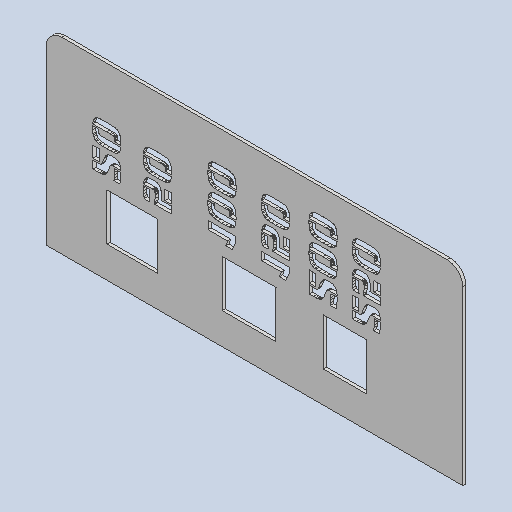
# Autodesk Inventor part: GBK-RK-0051 Cipolletti R
Saved by Autodesk Inventor 2026.2 (Build 302298000, 298)
## iProperties
Created: 2026-10-23
Part Number: GBK-RK-0051 Cipolletti R
Material: Generic
Description: Шкала расхода водослива, правая (трафарет, Saira Stencil)
Document SubType Name: Sheet Metal
Designer: admin
Density: 1 g/cm^3
Sheet Metal Rule: Default_mm
Appearance: Default
Flat Pattern Width: 12 cm
Flat Pattern Length: 26.6044 cm
Flat Pattern Area: 319.253 cm^2
Sheet Metal Width: 120,000 mm
Sheet Metal Length: 266,044 mm
Sheet Metal Area: 31925,333 mm^2
Author: admin
Autodesk Inventor part; units mm, degrees
(part 1 of 2)
ref_plane "YZ Plane" through (0, 0, 0) normal (1, 0, 0) x (0, 1, 0)
ref_plane "XZ Plane" through (0, 0, 0) normal (0, 1, 0) x (-1, 0, 0)
ref_plane "XY Plane" through (0, 0, 0) normal (0, 0, 1) x (1, 0, 0)
sketch "Sketch1" plane through (0, 0, 0) normal (0, 0, 1) x (1, 0, 0)
  line L0 (0, 0) -> (266.0444, 0)
  line L1 (266.0444, 0) -> (266.0444, 120)
  line L2 (266.0444, 120) -> (0, 120)
  line L3 (0, 120) -> (0, 0)
extrude "Plate1" add sketch "Sketch1" along normal blind 2
sketch "Sketch3" plane through (0, 0, 0) normal (0, 0, -1) x (-1, 0, 0)
  line L0 (-38.8424, 20) -> (-71.2409, 20)
  line L1 (-71.2409, 20) -> (-71.2409, 50)
  line L2 (-71.2409, 50) -> (-38.8424, 50)
  line L3 (-38.8424, 50) -> (-38.8424, 20)
  line L4 (-112.4742, 20) -> (-146.7233, 20)
  line L5 (-146.7233, 20) -> (-146.7233, 50)
  line L6 (-146.7233, 50) -> (-112.4742, 50)
  line L7 (-112.4742, 50) -> (-112.4742, 20)
  line L8 (-177.0426, 20) -> (-204.7056, 20)
  line L9 (-204.7056, 20) -> (-204.7056, 50)
  line L10 (-204.7056, 50) -> (-177.0426, 50)
  line L11 (-177.0426, 50) -> (-177.0426, 20)
  line L12 (-46.9971, 57.3557) -> (-47.3068, 58.9923)
  line L13 (-47.3068, 58.9923) -> (-47.6264, 62.3422)
  line L14 (-47.6264, 62.3422) -> (-47.6363, 64.0553)
  line L15 (-47.6363, 64.0553) -> (-43.6492, 64.0553)
  line L16 (-43.6492, 64.0553) -> (-43.7063, 63.3092)
  line L17 (-43.7063, 63.3092) -> (-43.7252, 62.0377)
  line L18 (-43.7252, 62.0377) -> (-43.6743, 60.6366)
  line L19 (-43.6743, 60.6366) -> (-43.5214, 58.9416)
  line L20 (-43.5214, 58.9416) -> (-43.3176, 57.3557)
  line L21 (-43.3176, 57.3557) -> (-46.9971, 57.3557)
  line L22 (-32.4233, 57) -> (-33.9254, 57.0251)
  line L23 (-33.9254, 57.0251) -> (-35.1079, 57.1)
  line L24 (-35.1079, 57.1) -> (-35.6017, 57.1662)
  line L25 (-35.6017, 57.1662) -> (-36.4848, 57.3838)
  line L26 (-36.4848, 57.3838) -> (-36.8737, 57.5354)
  line L27 (-36.8737, 57.5354) -> (-37.2557, 57.7333)
  line L28 (-37.2557, 57.7333) -> (-37.9388, 58.2388)
  line L29 (-37.9388, 58.2388) -> (-38.24, 58.5461)
  line L30 (-38.24, 58.5461) -> (-38.5205, 58.9015)
  line L31 (-38.5205, 58.9015) -> (-39.0401, 59.7903)
  line L32 (-39.0401, 59.7903) -> (-39.2786, 60.3239)
  line L33 (-39.2786, 60.3239) -> (-40.4773, 63.3161)
  line L34 (-40.4773, 63.3161) -> (-40.6989, 63.8374)
  line L35 (-40.6989, 63.8374) -> (-40.9007, 64.2831)
  line L36 (-40.9007, 64.2831) -> (-41.0894, 64.6306)
  line L37 (-41.0894, 64.6306) -> (-41.2722, 64.8502)
  line L38 (-41.2722, 64.8502) -> (-41.467, 64.9952)
  line L39 (-41.467, 64.9952) -> (-41.6917, 65.078)
  line L40 (-41.6917, 65.078) -> (-41.9894, 65.1169)
  line L41 (-41.9894, 65.1169) -> (-42.3949, 65.1299)
  line L42 (-42.3949, 65.1299) -> (-47.6123, 65.1299)
  line L43 (-47.6123, 65.1299) -> (-47.5003, 66.2705)
  line L44 (-47.5003, 66.2705) -> (-47.3167, 67.2393)
  line L45 (-47.3167, 67.2393) -> (-47.1917, 67.6655)
  line L46 (-47.1917, 67.6655) -> (-46.8401, 68.4267)
  line L47 (-46.8401, 68.4267) -> (-46.6136, 68.7614)
  line L48 (-46.6136, 68.7614) -> (-46.2996, 69.1088)
  line L49 (-46.2996, 69.1088) -> (-45.5137, 69.6647)
  line L50 (-45.5137, 69.6647) -> (-44.5168, 70.0352)
  line L51 (-44.5168, 70.0352) -> (-43.3092, 70.2203)
  line L52 (-43.3092, 70.2203) -> (-42.6265, 70.2436)
  line L53 (-42.6265, 70.2436) -> (-41.4782, 70.1924)
  line L54 (-41.4782, 70.1924) -> (-40.0487, 69.9237)
  line L55 (-40.0487, 69.9237) -> (-39.2911, 69.6166)
  line L56 (-39.2911, 69.6166) -> (-38.971, 69.4246)
  line L57 (-38.971, 69.4246) -> (-38.6913, 69.2178)
  line L58 (-38.6913, 69.2178) -> (-38.1799, 68.7128)
  line L59 (-38.1799, 68.7128) -> (-37.5328, 67.7279)
  line L60 (-37.5328, 67.7279) -> (-37.1813, 66.9197)
  line L61 (-37.1813, 66.9197) -> (-35.775, 63.2882)
  line L62 (-35.775, 63.2882) -> (-35.6011, 62.8697)
  line L63 (-35.6011, 62.8697) -> (-35.4396, 62.5332)
  line L64 (-35.4396, 62.5332) -> (-35.2877, 62.2824)
  line L65 (-35.2877, 62.2824) -> (-35.1358, 62.1136)
  line L66 (-35.1358, 62.1136) -> (-34.955, 62.0109)
  line L67 (-34.955, 62.0109) -> (-34.7244, 61.9579)
  line L68 (-34.7244, 61.9579) -> (-34.3859, 61.9398)
  line L69 (-34.3859, 61.9398) -> (-33.8814, 61.9339)
  line L70 (-33.8814, 61.9339) -> (-29.8424, 61.9339)
  line L71 (-29.8424, 61.9339) -> (-29.8424, 57)
  line L72 (-29.8424, 57) -> (-32.4233, 57)
  line L73 (-33.8295, 63.0085) -> (-33.8295, 70.2436)
  line L74 (-33.8295, 70.2436) -> (-29.8424, 70.2436)
  line L75 (-29.8424, 70.2436) -> (-29.8424, 63.0085)
  line L76 (-29.8424, 63.0085) -> (-33.8295, 63.0085)
  line L77 (-38.6394, 81.9568) -> (-40.4783, 81.9499)
  line L78 (-40.4783, 81.9499) -> (-41.5519, 81.929)
  line L79 (-41.5519, 81.929) -> (-42.4667, 81.852)
  line L80 (-42.4667, 81.852) -> (-43.0619, 81.7252)
  line L81 (-43.0619, 81.7252) -> (-43.2596, 81.6234)
  line L82 (-43.2596, 81.6234) -> (-43.5332, 81.3478)
  line L83 (-43.5332, 81.3478) -> (-43.6094, 81.1739)
  line L84 (-43.6094, 81.1739) -> (-43.6963, 80.6805)
  line L85 (-43.6963, 80.6805) -> (-43.7252, 79.9354)
  line L86 (-43.7252, 79.9354) -> (-43.7121, 79.5069)
  line L87 (-43.7121, 79.5069) -> (-43.6733, 78.9886)
  line L88 (-43.6733, 78.9886) -> (-47.6123, 78.9886)
  line L89 (-47.6123, 78.9886) -> (-47.6302, 79.1814)
  line L90 (-47.6302, 79.1814) -> (-47.6363, 79.4481)
  line L91 (-47.6363, 79.4481) -> (-47.6363, 79.9354)
  line L92 (-47.6363, 79.9354) -> (-47.6082, 81.2011)
  line L93 (-47.6082, 81.2011) -> (-47.3845, 83.2726)
  line L94 (-47.3845, 83.2726) -> (-47.1889, 84.0782)
  line L95 (-47.1889, 84.0782) -> (-46.9291, 84.7591)
  line L96 (-46.9291, 84.7591) -> (-46.194, 85.832)
  line L97 (-46.194, 85.832) -> (-45.7187, 86.2237)
  line L98 (-45.7187, 86.2237) -> (-45.2102, 86.5128)
  line L99 (-45.2102, 86.5128) -> (-43.9719, 86.9084)
  line L100 (-43.9719, 86.9084) -> (-43.2417, 87.0147)
  line L101 (-43.2417, 87.0147) -> (-41.3241, 87.1316)
  line L102 (-41.3241, 87.1316) -> (-38.6394, 87.1705)
  line L103 (-38.6394, 87.1705) -> (-36.2084, 87.1416)
  line L104 (-36.2084, 87.1416) -> (-34.4447, 87.0546)
  line L105 (-34.4447, 87.0546) -> (-33.7579, 86.9766)
  line L106 (-33.7579, 86.9766) -> (-32.5555, 86.689)
  line L107 (-32.5555, 86.689) -> (-32.0398, 86.4793)
  line L108 (-32.0398, 86.4793) -> (-31.5368, 86.1891)
  line L109 (-31.5368, 86.1891) -> (-30.7258, 85.4022)
  line L110 (-30.7258, 85.4022) -> (-30.4177, 84.9054)
  line L111 (-30.4177, 84.9054) -> (-30.1671, 84.3239)
  line L112 (-30.1671, 84.3239) -> (-29.8156, 82.8499)
  line L113 (-29.8156, 82.8499) -> (-29.7146, 81.9568)
  line L114 (-29.7146, 81.9568) -> (-38.6394, 81.9568)
  line L115 (-29.6386, 79.9354) -> (-29.6665, 78.6795)
  line L116 (-29.6665, 78.6795) -> (-29.8905, 76.6141)
  line L117 (-29.8905, 76.6141) -> (-30.0861, 75.8046)
  line L118 (-30.0861, 75.8046) -> (-30.3474, 75.1184)
  line L119 (-30.3474, 75.1184) -> (-31.0942, 74.0399)
  line L120 (-31.0942, 74.0399) -> (-31.5803, 73.6472)
  line L121 (-31.5803, 73.6472) -> (-32.0886, 73.358)
  line L122 (-32.0886, 73.358) -> (-33.3151, 72.9604)
  line L123 (-33.3151, 72.9604) -> (-34.0333, 72.8523)
  line L124 (-34.0333, 72.8523) -> (-35.9399, 72.7385)
  line L125 (-35.9399, 72.7385) -> (-38.6394, 72.7004)
  line L126 (-38.6394, 72.7004) -> (-41.0674, 72.7285)
  line L127 (-41.0674, 72.7285) -> (-42.8303, 72.8124)
  line L128 (-42.8303, 72.8124) -> (-43.5183, 72.8919)
  line L129 (-43.5183, 72.8919) -> (-44.7208, 73.1816)
  line L130 (-44.7208, 73.1816) -> (-45.2352, 73.3915)
  line L131 (-45.2352, 73.3915) -> (-45.7397, 73.6814)
  line L132 (-45.7397, 73.6814) -> (-46.5507, 74.4666)
  line L133 (-46.5507, 74.4666) -> (-46.8573, 74.9616)
  line L134 (-46.8573, 74.9616) -> (-47.1078, 75.5446)
  line L135 (-47.1078, 75.5446) -> (-47.4594, 77.0209)
  line L136 (-47.4594, 77.0209) -> (-47.5604, 77.914)
  line L137 (-47.5604, 77.914) -> (-38.6394, 77.914)
  line L138 (-38.6394, 77.914) -> (-36.8156, 77.9209)
  line L139 (-36.8156, 77.9209) -> (-35.7471, 77.9419)
  line L140 (-35.7471, 77.9419) -> (-34.8523, 78.025)
  line L141 (-34.8523, 78.025) -> (-34.213, 78.1697)
  line L142 (-34.213, 78.1697) -> (-34.0169, 78.2707)
  line L143 (-34.0169, 78.2707) -> (-33.7434, 78.5381)
  line L144 (-33.7434, 78.5381) -> (-33.6656, 78.7051)
  line L145 (-33.6656, 78.7051) -> (-33.5787, 79.1924)
  line L146 (-33.5787, 79.1924) -> (-33.5498, 79.9354)
  line L147 (-33.5498, 79.9354) -> (-33.5498, 80.4468)
  line L148 (-33.5498, 80.4468) -> (-33.5628, 80.6457)
  line L149 (-33.5628, 80.6457) -> (-33.6017, 80.8822)
  line L150 (-33.6017, 80.8822) -> (-29.6627, 80.8822)
  line L151 (-29.6627, 80.8822) -> (-29.6448, 80.6894)
  line L152 (-29.6448, 80.6894) -> (-29.6386, 80.4228)
  line L153 (-29.6386, 80.4228) -> (-29.6386, 79.9354)
  line L154 (-67.7381, 64.978) -> (-68.3213, 64.955)
  line L155 (-68.3213, 64.955) -> (-68.7449, 64.8863)
  line L156 (-68.7449, 64.8863) -> (-69.0505, 64.7502)
  line L157 (-69.0505, 64.7502) -> (-69.2721, 64.5186)
  line L158 (-69.2721, 64.5186) -> (-69.423, 64.1841)
  line L159 (-69.423, 64.1841) -> (-69.5158, 63.7477)
  line L160 (-69.5158, 63.7477) -> (-69.5639, 63.1553)
  line L161 (-69.5639, 63.1553) -> (-69.5797, 62.3453)
  line L162 (-69.5797, 62.3453) -> (-69.5409, 60.6056)
  line L163 (-69.5409, 60.6056) -> (-69.424, 58.7657)
  line L164 (-69.424, 58.7657) -> (-69.3419, 57.7739)
  line L165 (-69.3419, 57.7739) -> (-69.2962, 57.2038)
  line L166 (-69.2962, 57.2038) -> (-79.831, 57.2038)
  line L167 (-79.831, 57.2038) -> (-79.831, 61.5263)
  line L168 (-79.831, 61.5263) -> (-73.339, 61.5263)
  line L169 (-73.339, 61.5263) -> (-73.415, 62.3693)
  line L170 (-73.415, 62.3693) -> (-73.472, 63.8784)
  line L171 (-73.472, 63.8784) -> (-73.4909, 64.8742)
  line L172 (-73.4909, 64.8742) -> (-73.4681, 65.6073)
  line L173 (-73.4681, 65.6073) -> (-73.2858, 66.9051)
  line L174 (-73.2858, 66.9051) -> (-72.9212, 67.9787)
  line L175 (-72.9212, 67.9787) -> (-72.3746, 68.8281)
  line L176 (-72.3746, 68.8281) -> (-72.0327, 69.1689)
  line L177 (-72.0327, 69.1689) -> (-71.6827, 69.4295)
  line L178 (-71.6827, 69.4295) -> (-70.8717, 69.825)
  line L179 (-70.8717, 69.825) -> (-70.4107, 69.96)
  line L180 (-70.4107, 69.96) -> (-69.908, 70.0613)
  line L181 (-69.908, 70.0613) -> (-68.7636, 70.1771)
  line L182 (-68.7636, 70.1771) -> (-68.1216, 70.1916)
  line L183 (-68.1216, 70.1916) -> (-67.397, 70.1771)
  line L184 (-67.397, 70.1771) -> (-66.1306, 70.0613)
  line L185 (-66.1306, 70.0613) -> (-65.5888, 69.96)
  line L186 (-65.5888, 69.96) -> (-65.0966, 69.825)
  line L187 (-65.0966, 69.825) -> (-64.2278, 69.4295)
  line L188 (-64.2278, 69.4295) -> (-63.8509, 69.1689)
  line L189 (-63.8509, 69.1689) -> (-63.5116, 68.8593)
  line L190 (-63.5116, 68.8593) -> (-62.9422, 68.0603)
  line L191 (-62.9422, 68.0603) -> (-62.7124, 67.5709)
  line L192 (-62.7124, 67.5709) -> (-62.5191, 67.0207)
  line L193 (-62.5191, 67.0207) -> (-62.2314, 65.7244)
  line L194 (-62.2314, 65.7244) -> (-62.1371, 64.978)
  line L195 (-62.1371, 64.978) -> (-67.7381, 64.978)
  line L196 (-79.831, 62.601) -> (-79.831, 68.8892)
  line L197 (-79.831, 68.8892) -> (-75.868, 68.8892)
  line L198 (-75.868, 68.8892) -> (-75.868, 62.601)
  line L199 (-75.868, 62.601) -> (-79.831, 62.601)
  line L200 (-62.0371, 62.6769) -> (-62.0821, 61.1249)
  line L201 (-62.0821, 61.1249) -> (-62.2169, 59.5929)
  line L202 (-62.2169, 59.5929) -> (-62.4127, 58.1856)
  line L203 (-62.4127, 58.1856) -> (-62.6485, 57)
  line L204 (-62.6485, 57) -> (-66.3078, 57)
  line L205 (-66.3078, 57) -> (-66.161, 58.4221)
  line L206 (-66.161, 58.4221) -> (-65.9933, 60.9789)
  line L207 (-65.9933, 60.9789) -> (-65.9723, 62.1136)
  line L208 (-65.9723, 62.1136) -> (-65.9854, 63.1624)
  line L209 (-65.9854, 63.1624) -> (-66.0242, 63.9034)
  line L210 (-66.0242, 63.9034) -> (-62.0611, 63.9034)
  line L211 (-62.0611, 63.9034) -> (-62.0433, 63.3931)
  line L212 (-62.0433, 63.3931) -> (-62.0371, 62.6769)
  line L213 (-71.0379, 81.853) -> (-72.8767, 81.8461)
  line L214 (-72.8767, 81.8461) -> (-73.9504, 81.8252)
  line L215 (-73.9504, 81.8252) -> (-74.8652, 81.7482)
  line L216 (-74.8652, 81.7482) -> (-75.4604, 81.6214)
  line L217 (-75.4604, 81.6214) -> (-75.6581, 81.5194)
  line L218 (-75.6581, 81.5194) -> (-75.9316, 81.2438)
  line L219 (-75.9316, 81.2438) -> (-76.0078, 81.0701)
  line L220 (-76.0078, 81.0701) -> (-76.0948, 80.5767)
  line L221 (-76.0948, 80.5767) -> (-76.1236, 79.8316)
  line L222 (-76.1236, 79.8316) -> (-76.1106, 79.4031)
  line L223 (-76.1106, 79.4031) -> (-76.0717, 78.8848)
  line L224 (-76.0717, 78.8848) -> (-80.0108, 78.8848)
  line L225 (-80.0108, 78.8848) -> (-80.0287, 79.0776)
  line L226 (-80.0287, 79.0776) -> (-80.0348, 79.3443)
  line L227 (-80.0348, 79.3443) -> (-80.0348, 79.8316)
  line L228 (-80.0348, 79.8316) -> (-80.0067, 81.0972)
  line L229 (-80.0067, 81.0972) -> (-79.783, 83.1688)
  line L230 (-79.783, 83.1688) -> (-79.5874, 83.9744)
  line L231 (-79.5874, 83.9744) -> (-79.3276, 84.6553)
  line L232 (-79.3276, 84.6553) -> (-78.5925, 85.7279)
  line L233 (-78.5925, 85.7279) -> (-78.1172, 86.1199)
  line L234 (-78.1172, 86.1199) -> (-77.6086, 86.4088)
  line L235 (-77.6086, 86.4088) -> (-76.3704, 86.8043)
  line L236 (-76.3704, 86.8043) -> (-75.6402, 86.9107)
  line L237 (-75.6402, 86.9107) -> (-73.7225, 87.0275)
  line L238 (-73.7225, 87.0275) -> (-71.0379, 87.0666)
  line L239 (-71.0379, 87.0666) -> (-68.6069, 87.0375)
  line L240 (-68.6069, 87.0375) -> (-66.8432, 86.9508)
  line L241 (-66.8432, 86.9508) -> (-66.1564, 86.8728)
  line L242 (-66.1564, 86.8728) -> (-64.9539, 86.5852)
  line L243 (-64.9539, 86.5852) -> (-64.4382, 86.3755)
  line L244 (-64.4382, 86.3755) -> (-63.9353, 86.0853)
  line L245 (-63.9353, 86.0853) -> (-63.1243, 85.2984)
  line L246 (-63.1243, 85.2984) -> (-62.8162, 84.8013)
  line L247 (-62.8162, 84.8013) -> (-62.5656, 84.2201)
  line L248 (-62.5656, 84.2201) -> (-62.214, 82.7459)
  line L249 (-62.214, 82.7459) -> (-62.1131, 81.853)
  line L250 (-62.1131, 81.853) -> (-71.0379, 81.853)
  line L251 (-62.0371, 79.8316) -> (-62.065, 78.5757)
  line L252 (-62.065, 78.5757) -> (-62.289, 76.5103)
  line L253 (-62.289, 76.5103) -> (-62.4846, 75.7008)
  line L254 (-62.4846, 75.7008) -> (-62.7459, 75.0146)
  line L255 (-62.7459, 75.0146) -> (-63.4927, 73.9359)
  line L256 (-63.4927, 73.9359) -> (-63.9788, 73.5434)
  line L257 (-63.9788, 73.5434) -> (-64.4871, 73.2539)
  line L258 (-64.4871, 73.2539) -> (-65.7136, 72.8566)
  line L259 (-65.7136, 72.8566) -> (-66.4318, 72.7485)
  line L260 (-66.4318, 72.7485) -> (-68.3384, 72.6344)
  line L261 (-68.3384, 72.6344) -> (-71.0379, 72.5966)
  line L262 (-71.0379, 72.5966) -> (-73.4658, 72.6245)
  line L263 (-73.4658, 72.6245) -> (-75.2288, 72.7086)
  line L264 (-75.2288, 72.7086) -> (-75.9168, 72.7881)
  line L265 (-75.9168, 72.7881) -> (-77.1193, 73.0778)
  line L266 (-77.1193, 73.0778) -> (-77.6337, 73.2877)
  line L267 (-77.6337, 73.2877) -> (-78.1382, 73.5776)
  line L268 (-78.1382, 73.5776) -> (-78.9492, 74.3626)
  line L269 (-78.9492, 74.3626) -> (-79.2558, 74.8578)
  line L270 (-79.2558, 74.8578) -> (-79.5063, 75.4408)
  line L271 (-79.5063, 75.4408) -> (-79.8579, 76.9168)
  line L272 (-79.8579, 76.9168) -> (-79.9589, 77.8102)
  line L273 (-79.9589, 77.8102) -> (-71.0379, 77.8102)
  line L274 (-71.0379, 77.8102) -> (-69.2141, 77.8171)
  line L275 (-69.2141, 77.8171) -> (-68.1456, 77.8381)
  line L276 (-68.1456, 77.8381) -> (-67.2507, 77.9209)
  line L277 (-67.2507, 77.9209) -> (-66.6115, 78.0659)
  line L278 (-66.6115, 78.0659) -> (-66.4154, 78.1666)
  line L279 (-66.4154, 78.1666) -> (-66.1418, 78.4343)
  line L280 (-66.1418, 78.4343) -> (-66.0641, 78.601)
  line L281 (-66.0641, 78.601) -> (-65.9772, 79.0886)
  line L282 (-65.9772, 79.0886) -> (-65.9483, 79.8316)
  line L283 (-65.9483, 79.8316) -> (-65.9483, 80.343)
  line L284 (-65.9483, 80.343) -> (-65.9613, 80.5416)
  line L285 (-65.9613, 80.5416) -> (-66.0002, 80.7784)
  line L286 (-66.0002, 80.7784) -> (-62.0611, 80.7784)
  line L287 (-62.0611, 80.7784) -> (-62.0433, 80.5856)
  line L288 (-62.0433, 80.5856) -> (-62.0371, 80.3189)
  line L289 (-62.0371, 80.3189) -> (-62.0371, 79.8316)
  line L290 (-115.9267, 60.2479) -> (-114.7002, 57)
  line L291 (-114.7002, 57) -> (-118.6873, 57)
  line L292 (-118.6873, 57) -> (-121.0644, 61.9618)
  line L293 (-121.0644, 61.9618) -> (-121.0644, 65.3616)
  line L294 (-121.0644, 65.3616) -> (-103.4742, 65.3616)
  line L295 (-103.4742, 65.3616) -> (-103.4742, 60.2479)
  line L296 (-103.4742, 60.2479) -> (-115.9267, 60.2479)
  line L297 (-112.2712, 77.4824) -> (-114.1101, 77.4755)
  line L298 (-114.1101, 77.4755) -> (-115.1837, 77.4545)
  line L299 (-115.1837, 77.4545) -> (-116.0985, 77.3776)
  line L300 (-116.0985, 77.3776) -> (-116.6938, 77.2508)
  line L301 (-116.6938, 77.2508) -> (-116.8914, 77.149)
  line L302 (-116.8914, 77.149) -> (-117.165, 76.8734)
  line L303 (-117.165, 76.8734) -> (-117.2412, 76.6995)
  line L304 (-117.2412, 76.6995) -> (-117.3281, 76.2061)
  line L305 (-117.3281, 76.2061) -> (-117.357, 75.461)
  line L306 (-117.357, 75.461) -> (-117.344, 75.0325)
  line L307 (-117.344, 75.0325) -> (-117.3051, 74.5142)
  line L308 (-117.3051, 74.5142) -> (-121.2441, 74.5142)
  line L309 (-121.2441, 74.5142) -> (-121.262, 74.707)
  line L310 (-121.262, 74.707) -> (-121.2682, 74.9737)
  line L311 (-121.2682, 74.9737) -> (-121.2682, 75.461)
  line L312 (-121.2682, 75.461) -> (-121.24, 76.7266)
  line L313 (-121.24, 76.7266) -> (-121.0163, 78.7982)
  line L314 (-121.0163, 78.7982) -> (-120.8207, 79.6038)
  line L315 (-120.8207, 79.6038) -> (-120.5609, 80.2847)
  line L316 (-120.5609, 80.2847) -> (-119.8259, 81.3575)
  line L317 (-119.8259, 81.3575) -> (-119.3505, 81.7492)
  line L318 (-119.3505, 81.7492) -> (-118.842, 82.0384)
  line L319 (-118.842, 82.0384) -> (-117.6037, 82.4339)
  line L320 (-117.6037, 82.4339) -> (-116.8735, 82.5403)
  line L321 (-116.8735, 82.5403) -> (-114.9559, 82.6572)
  line L322 (-114.9559, 82.6572) -> (-112.2712, 82.696)
  line L323 (-112.2712, 82.696) -> (-109.8402, 82.6671)
  line L324 (-109.8402, 82.6671) -> (-108.0765, 82.5802)
  line L325 (-108.0765, 82.5802) -> (-107.3898, 82.5022)
  line L326 (-107.3898, 82.5022) -> (-106.1873, 82.2146)
  line L327 (-106.1873, 82.2146) -> (-105.6716, 82.0049)
  line L328 (-105.6716, 82.0049) -> (-105.1686, 81.7147)
  line L329 (-105.1686, 81.7147) -> (-104.3576, 80.9277)
  line L330 (-104.3576, 80.9277) -> (-104.0495, 80.4309)
  line L331 (-104.0495, 80.4309) -> (-103.799, 79.8495)
  line L332 (-103.799, 79.8495) -> (-103.4474, 78.3755)
  line L333 (-103.4474, 78.3755) -> (-103.3464, 77.4824)
  line L334 (-103.3464, 77.4824) -> (-112.2712, 77.4824)
  line L335 (-103.2705, 75.461) -> (-103.2983, 74.2051)
  line L336 (-103.2983, 74.2051) -> (-103.5223, 72.1397)
  line L337 (-103.5223, 72.1397) -> (-103.7179, 71.3302)
  line L338 (-103.7179, 71.3302) -> (-103.9792, 70.6439)
  line L339 (-103.9792, 70.6439) -> (-104.7261, 69.5655)
  line L340 (-104.7261, 69.5655) -> (-105.2121, 69.1728)
  line L341 (-105.2121, 69.1728) -> (-105.7204, 68.8836)
  line L342 (-105.7204, 68.8836) -> (-106.9469, 68.486)
  line L343 (-106.9469, 68.486) -> (-107.6651, 68.3778)
  line L344 (-107.6651, 68.3778) -> (-109.5717, 68.2641)
  line L345 (-109.5717, 68.2641) -> (-112.2712, 68.226)
  line L346 (-112.2712, 68.226) -> (-114.6992, 68.2541)
  line L347 (-114.6992, 68.2541) -> (-116.4621, 68.338)
  line L348 (-116.4621, 68.338) -> (-117.1502, 68.4175)
  line L349 (-117.1502, 68.4175) -> (-118.3526, 68.7072)
  line L350 (-118.3526, 68.7072) -> (-118.8671, 68.9171)
  line L351 (-118.8671, 68.9171) -> (-119.3715, 69.207)
  line L352 (-119.3715, 69.207) -> (-120.1825, 69.992)
  line L353 (-120.1825, 69.992) -> (-120.4891, 70.4872)
  line L354 (-120.4891, 70.4872) -> (-120.7397, 71.0702)
  line L355 (-120.7397, 71.0702) -> (-121.0912, 72.5465)
  line L356 (-121.0912, 72.5465) -> (-121.1922, 73.4396)
  line L357 (-121.1922, 73.4396) -> (-112.2712, 73.4396)
  line L358 (-112.2712, 73.4396) -> (-110.4475, 73.4465)
  line L359 (-110.4475, 73.4465) -> (-109.379, 73.4674)
  line L360 (-109.379, 73.4674) -> (-108.4841, 73.5503)
  line L361 (-108.4841, 73.5503) -> (-107.8449, 73.6953)
  line L362 (-107.8449, 73.6953) -> (-107.6488, 73.796)
  line L363 (-107.6488, 73.796) -> (-107.3752, 74.0637)
  line L364 (-107.3752, 74.0637) -> (-107.2975, 74.2307)
  line L365 (-107.2975, 74.2307) -> (-107.2105, 74.718)
  line L366 (-107.2105, 74.718) -> (-107.1816, 75.461)
  line L367 (-107.1816, 75.461) -> (-107.1816, 75.9724)
  line L368 (-107.1816, 75.9724) -> (-107.1947, 76.171)
  line L369 (-107.1947, 76.171) -> (-107.2335, 76.4078)
  line L370 (-107.2335, 76.4078) -> (-103.2945, 76.4078)
  line L371 (-103.2945, 76.4078) -> (-103.2766, 76.215)
  line L372 (-103.2766, 76.215) -> (-103.2705, 75.9483)
  line L373 (-103.2705, 75.9483) -> (-103.2705, 75.461)
  line L374 (-112.2712, 94.3574) -> (-114.1101, 94.3505)
  line L375 (-114.1101, 94.3505) -> (-115.1837, 94.3295)
  line L376 (-115.1837, 94.3295) -> (-116.0985, 94.2526)
  line L377 (-116.0985, 94.2526) -> (-116.6938, 94.1258)
  line L378 (-116.6938, 94.1258) -> (-116.8914, 94.024)
  line L379 (-116.8914, 94.024) -> (-117.165, 93.7484)
  line L380 (-117.165, 93.7484) -> (-117.2412, 93.5745)
  line L381 (-117.2412, 93.5745) -> (-117.3281, 93.0811)
  line L382 (-117.3281, 93.0811) -> (-117.357, 92.336)
  line L383 (-117.357, 92.336) -> (-117.344, 91.9075)
  line L384 (-117.344, 91.9075) -> (-117.3051, 91.3892)
  line L385 (-117.3051, 91.3892) -> (-121.2441, 91.3892)
  line L386 (-121.2441, 91.3892) -> (-121.262, 91.582)
  line L387 (-121.262, 91.582) -> (-121.2682, 91.8487)
  line L388 (-121.2682, 91.8487) -> (-121.2682, 92.336)
  line L389 (-121.2682, 92.336) -> (-121.24, 93.6016)
  line L390 (-121.24, 93.6016) -> (-121.0163, 95.6732)
  line L391 (-121.0163, 95.6732) -> (-120.8207, 96.4788)
  line L392 (-120.8207, 96.4788) -> (-120.5609, 97.1597)
  line L393 (-120.5609, 97.1597) -> (-119.8259, 98.2325)
  line L394 (-119.8259, 98.2325) -> (-119.3505, 98.6242)
  line L395 (-119.3505, 98.6242) -> (-118.842, 98.9134)
  line L396 (-118.842, 98.9134) -> (-117.6037, 99.3089)
  line L397 (-117.6037, 99.3089) -> (-116.8735, 99.4153)
  line L398 (-116.8735, 99.4153) -> (-114.9559, 99.5322)
  line L399 (-114.9559, 99.5322) -> (-112.2712, 99.571)
  line L400 (-112.2712, 99.571) -> (-109.8402, 99.5421)
  line L401 (-109.8402, 99.5421) -> (-108.0765, 99.4552)
  line L402 (-108.0765, 99.4552) -> (-107.3898, 99.3772)
  line L403 (-107.3898, 99.3772) -> (-106.1873, 99.0896)
  line L404 (-106.1873, 99.0896) -> (-105.6716, 98.8799)
  line L405 (-105.6716, 98.8799) -> (-105.1686, 98.5897)
  line L406 (-105.1686, 98.5897) -> (-104.3576, 97.8027)
  line L407 (-104.3576, 97.8027) -> (-104.0495, 97.3059)
  line L408 (-104.0495, 97.3059) -> (-103.799, 96.7245)
  line L409 (-103.799, 96.7245) -> (-103.4474, 95.2505)
  line L410 (-103.4474, 95.2505) -> (-103.3464, 94.3574)
  line L411 (-103.3464, 94.3574) -> (-112.2712, 94.3574)
  line L412 (-103.2705, 92.336) -> (-103.2983, 91.0801)
  line L413 (-103.2983, 91.0801) -> (-103.5223, 89.0147)
  line L414 (-103.5223, 89.0147) -> (-103.7179, 88.2052)
  line L415 (-103.7179, 88.2052) -> (-103.9792, 87.5189)
  line L416 (-103.9792, 87.5189) -> (-104.7261, 86.4405)
  line L417 (-104.7261, 86.4405) -> (-105.2121, 86.0478)
  line L418 (-105.2121, 86.0478) -> (-105.7204, 85.7586)
  line L419 (-105.7204, 85.7586) -> (-106.9469, 85.361)
  line L420 (-106.9469, 85.361) -> (-107.6651, 85.2528)
  line L421 (-107.6651, 85.2528) -> (-109.5717, 85.1391)
  line L422 (-109.5717, 85.1391) -> (-112.2712, 85.101)
  line L423 (-112.2712, 85.101) -> (-114.6992, 85.1291)
  line L424 (-114.6992, 85.1291) -> (-116.4621, 85.213)
  line L425 (-116.4621, 85.213) -> (-117.1502, 85.2925)
  line L426 (-117.1502, 85.2925) -> (-118.3526, 85.5822)
  line L427 (-118.3526, 85.5822) -> (-118.8671, 85.7921)
  line L428 (-118.8671, 85.7921) -> (-119.3715, 86.082)
  line L429 (-119.3715, 86.082) -> (-120.1825, 86.867)
  line L430 (-120.1825, 86.867) -> (-120.4891, 87.3622)
  line L431 (-120.4891, 87.3622) -> (-120.7397, 87.9452)
  line L432 (-120.7397, 87.9452) -> (-121.0912, 89.4215)
  line L433 (-121.0912, 89.4215) -> (-121.1922, 90.3146)
  line L434 (-121.1922, 90.3146) -> (-112.2712, 90.3146)
  line L435 (-112.2712, 90.3146) -> (-110.4475, 90.3215)
  line L436 (-110.4475, 90.3215) -> (-109.379, 90.3424)
  line L437 (-109.379, 90.3424) -> (-108.4841, 90.4253)
  line L438 (-108.4841, 90.4253) -> (-107.8449, 90.5703)
  line L439 (-107.8449, 90.5703) -> (-107.6488, 90.671)
  line L440 (-107.6488, 90.671) -> (-107.3752, 90.9387)
  line L441 (-107.3752, 90.9387) -> (-107.2975, 91.1057)
  line L442 (-107.2975, 91.1057) -> (-107.2105, 91.593)
  line L443 (-107.2105, 91.593) -> (-107.1816, 92.336)
  line L444 (-107.1816, 92.336) -> (-107.1816, 92.8474)
  line L445 (-107.1816, 92.8474) -> (-107.1947, 93.046)
  line L446 (-107.1947, 93.046) -> (-107.2335, 93.2828)
  line L447 (-107.2335, 93.2828) -> (-103.2945, 93.2828)
  line L448 (-103.2945, 93.2828) -> (-103.2766, 93.09)
  line L449 (-103.2766, 93.09) -> (-103.2705, 92.8233)
  line L450 (-103.2705, 92.8233) -> (-103.2705, 92.336)
  line L451 (-150.1758, 60.2479) -> (-148.9493, 57)
  line L452 (-148.9493, 57) -> (-152.9364, 57)
  line L453 (-152.9364, 57) -> (-155.3134, 61.9618)
  line L454 (-155.3134, 61.9618) -> (-155.3134, 65.3616)
  line L455 (-155.3134, 65.3616) -> (-137.7233, 65.3616)
  line L456 (-137.7233, 65.3616) -> (-137.7233, 60.2479)
  line L457 (-137.7233, 60.2479) -> (-150.1758, 60.2479)
  line L458 (-143.2205, 76.6635) -> (-143.8037, 76.6405)
  line L459 (-143.8037, 76.6405) -> (-144.2273, 76.5717)
  line L460 (-144.2273, 76.5717) -> (-144.5329, 76.4359)
  line L461 (-144.5329, 76.4359) -> (-144.7546, 76.204)
  line L462 (-144.7546, 76.204) -> (-144.9054, 75.8696)
  line L463 (-144.9054, 75.8696) -> (-144.9982, 75.4331)
  line L464 (-144.9982, 75.4331) -> (-145.0463, 74.8407)
  line L465 (-145.0463, 74.8407) -> (-145.0621, 74.0307)
  line L466 (-145.0621, 74.0307) -> (-145.0233, 72.2911)
  line L467 (-145.0233, 72.2911) -> (-144.9064, 70.4512)
  line L468 (-144.9064, 70.4512) -> (-144.8244, 69.4594)
  line L469 (-144.8244, 69.4594) -> (-144.7786, 68.8892)
  line L470 (-144.7786, 68.8892) -> (-155.3134, 68.8892)
  line L471 (-155.3134, 68.8892) -> (-155.3134, 73.2118)
  line L472 (-155.3134, 73.2118) -> (-148.8214, 73.2118)
  line L473 (-148.8214, 73.2118) -> (-148.8974, 74.0547)
  line L474 (-148.8974, 74.0547) -> (-148.9544, 75.5638)
  line L475 (-148.9544, 75.5638) -> (-148.9733, 76.5597)
  line L476 (-148.9733, 76.5597) -> (-148.9506, 77.2927)
  line L477 (-148.9506, 77.2927) -> (-148.7682, 78.5905)
  line L478 (-148.7682, 78.5905) -> (-148.4036, 79.6641)
  line L479 (-148.4036, 79.6641) -> (-147.857, 80.5138)
  line L480 (-147.857, 80.5138) -> (-147.5152, 80.8543)
  line L481 (-147.5152, 80.8543) -> (-147.1651, 81.1149)
  line L482 (-147.1651, 81.1149) -> (-146.3541, 81.5104)
  line L483 (-146.3541, 81.5104) -> (-145.8931, 81.6454)
  line L484 (-145.8931, 81.6454) -> (-145.3904, 81.7467)
  line L485 (-145.3904, 81.7467) -> (-144.246, 81.8625)
  line L486 (-144.246, 81.8625) -> (-143.604, 81.8771)
  line L487 (-143.604, 81.8771) -> (-142.8794, 81.8625)
  line L488 (-142.8794, 81.8625) -> (-141.613, 81.7467)
  line L489 (-141.613, 81.7467) -> (-141.0712, 81.6454)
  line L490 (-141.0712, 81.6454) -> (-140.579, 81.5104)
  line L491 (-140.579, 81.5104) -> (-139.7102, 81.1149)
  line L492 (-139.7102, 81.1149) -> (-139.3333, 80.8543)
  line L493 (-139.3333, 80.8543) -> (-138.994, 80.5447)
  line L494 (-138.994, 80.5447) -> (-138.4246, 79.7457)
  line L495 (-138.4246, 79.7457) -> (-138.1948, 79.2563)
  line L496 (-138.1948, 79.2563) -> (-138.0015, 78.7064)
  line L497 (-138.0015, 78.7064) -> (-137.7138, 77.4098)
  line L498 (-137.7138, 77.4098) -> (-137.6195, 76.6635)
  line L499 (-137.6195, 76.6635) -> (-143.2205, 76.6635)
  line L500 (-155.3134, 74.2864) -> (-155.3134, 80.5746)
  line L501 (-155.3134, 80.5746) -> (-151.3504, 80.5746)
  line L502 (-151.3504, 80.5746) -> (-151.3504, 74.2864)
  line L503 (-151.3504, 74.2864) -> (-155.3134, 74.2864)
  line L504 (-137.5195, 74.3623) -> (-137.5645, 72.8103)
  line L505 (-137.5645, 72.8103) -> (-137.6993, 71.2783)
  line L506 (-137.6993, 71.2783) -> (-137.8951, 69.871)
  line L507 (-137.8951, 69.871) -> (-138.1309, 68.6854)
  line L508 (-138.1309, 68.6854) -> (-141.7902, 68.6854)
  line L509 (-141.7902, 68.6854) -> (-141.6434, 70.1078)
  line L510 (-141.6434, 70.1078) -> (-141.4757, 72.6646)
  line L511 (-141.4757, 72.6646) -> (-141.4547, 73.7991)
  line L512 (-141.4547, 73.7991) -> (-141.4678, 74.8479)
  line L513 (-141.4678, 74.8479) -> (-141.5066, 75.5888)
  line L514 (-141.5066, 75.5888) -> (-137.5436, 75.5888)
  line L515 (-137.5436, 75.5888) -> (-137.5257, 75.0785)
  line L516 (-137.5257, 75.0785) -> (-137.5195, 74.3623)
  line L517 (-146.5203, 93.5385) -> (-148.3592, 93.5316)
  line L518 (-148.3592, 93.5316) -> (-149.4328, 93.5106)
  line L519 (-149.4328, 93.5106) -> (-150.3476, 93.4336)
  line L520 (-150.3476, 93.4336) -> (-150.9428, 93.3068)
  line L521 (-150.9428, 93.3068) -> (-151.1405, 93.2051)
  line L522 (-151.1405, 93.2051) -> (-151.414, 92.9292)
  line L523 (-151.414, 92.9292) -> (-151.4902, 92.7556)
  line L524 (-151.4902, 92.7556) -> (-151.5772, 92.2621)
  line L525 (-151.5772, 92.2621) -> (-151.6061, 91.517)
  line L526 (-151.6061, 91.517) -> (-151.593, 91.0885)
  line L527 (-151.593, 91.0885) -> (-151.5542, 90.5703)
  line L528 (-151.5542, 90.5703) -> (-155.4932, 90.5703)
  line L529 (-155.4932, 90.5703) -> (-155.5111, 90.763)
  line L530 (-155.5111, 90.763) -> (-155.5172, 91.0297)
  line L531 (-155.5172, 91.0297) -> (-155.5172, 91.517)
  line L532 (-155.5172, 91.517) -> (-155.4891, 92.7827)
  line L533 (-155.4891, 92.7827) -> (-155.2654, 94.8542)
  line L534 (-155.2654, 94.8542) -> (-155.0698, 95.6599)
  line L535 (-155.0698, 95.6599) -> (-154.81, 96.3407)
  line L536 (-154.81, 96.3407) -> (-154.0749, 97.4136)
  line L537 (-154.0749, 97.4136) -> (-153.5996, 97.8053)
  line L538 (-153.5996, 97.8053) -> (-153.0911, 98.0945)
  line L539 (-153.0911, 98.0945) -> (-151.8528, 98.4897)
  line L540 (-151.8528, 98.4897) -> (-151.1226, 98.5964)
  line L541 (-151.1226, 98.5964) -> (-149.205, 98.7132)
  line L542 (-149.205, 98.7132) -> (-146.5203, 98.7521)
  line L543 (-146.5203, 98.7521) -> (-144.0893, 98.7232)
  line L544 (-144.0893, 98.7232) -> (-142.3256, 98.6362)
  line L545 (-142.3256, 98.6362) -> (-141.6388, 98.5583)
  line L546 (-141.6388, 98.5583) -> (-140.4363, 98.2706)
  line L547 (-140.4363, 98.2706) -> (-139.9206, 98.061)
  line L548 (-139.9206, 98.061) -> (-139.4177, 97.7708)
  line L549 (-139.4177, 97.7708) -> (-138.6067, 96.9838)
  line L550 (-138.6067, 96.9838) -> (-138.2986, 96.487)
  line L551 (-138.2986, 96.487) -> (-138.048, 95.9056)
  line L552 (-138.048, 95.9056) -> (-137.6965, 94.4313)
  line L553 (-137.6965, 94.4313) -> (-137.5955, 93.5385)
  line L554 (-137.5955, 93.5385) -> (-146.5203, 93.5385)
  line L555 (-137.5195, 91.517) -> (-137.5474, 90.2611)
  line L556 (-137.5474, 90.2611) -> (-137.7714, 88.1957)
  line L557 (-137.7714, 88.1957) -> (-137.967, 87.3862)
  line L558 (-137.967, 87.3862) -> (-138.2283, 86.7)
  line L559 (-138.2283, 86.7) -> (-138.9751, 85.6213)
  line L560 (-138.9751, 85.6213) -> (-139.4612, 85.2288)
  line L561 (-139.4612, 85.2288) -> (-139.9695, 84.9394)
  line L562 (-139.9695, 84.9394) -> (-141.196, 84.542)
  line L563 (-141.196, 84.542) -> (-141.9142, 84.4339)
  line L564 (-141.9142, 84.4339) -> (-143.8208, 84.3201)
  line L565 (-143.8208, 84.3201) -> (-146.5203, 84.282)
  line L566 (-146.5203, 84.282) -> (-148.9482, 84.3099)
  line L567 (-148.9482, 84.3099) -> (-150.7112, 84.394)
  line L568 (-150.7112, 84.394) -> (-151.3992, 84.4735)
  line L569 (-151.3992, 84.4735) -> (-152.6017, 84.7632)
  line L570 (-152.6017, 84.7632) -> (-153.1161, 84.9731)
  line L571 (-153.1161, 84.9731) -> (-153.6206, 85.2631)
  line L572 (-153.6206, 85.2631) -> (-154.4316, 86.048)
  line L573 (-154.4316, 86.048) -> (-154.7382, 86.5433)
  line L574 (-154.7382, 86.5433) -> (-154.9887, 87.1262)
  line L575 (-154.9887, 87.1262) -> (-155.3403, 88.6025)
  line L576 (-155.3403, 88.6025) -> (-155.4413, 89.4956)
  line L577 (-155.4413, 89.4956) -> (-146.5203, 89.4956)
  line L578 (-146.5203, 89.4956) -> (-144.6965, 89.5025)
  line L579 (-144.6965, 89.5025) -> (-143.628, 89.5235)
  line L580 (-143.628, 89.5235) -> (-142.7331, 89.6063)
  line L581 (-142.7331, 89.6063) -> (-142.0939, 89.7513)
  line L582 (-142.0939, 89.7513) -> (-141.8978, 89.852)
  line L583 (-141.8978, 89.852) -> (-141.6242, 90.1197)
  line L584 (-141.6242, 90.1197) -> (-141.5465, 90.2867)
  line L585 (-141.5465, 90.2867) -> (-141.4596, 90.774)
  line L586 (-141.4596, 90.774) -> (-141.4307, 91.517)
  line L587 (-141.4307, 91.517) -> (-141.4307, 92.0284)
  line L588 (-141.4307, 92.0284) -> (-141.4437, 92.2271)
  line L589 (-141.4437, 92.2271) -> (-141.4826, 92.4638)
  line L590 (-141.4826, 92.4638) -> (-137.5436, 92.4638)
  line L591 (-137.5436, 92.4638) -> (-137.5257, 92.2711)
  line L592 (-137.5257, 92.2711) -> (-137.5195, 92.0044)
  line L593 (-137.5195, 92.0044) -> (-137.5195, 91.517)
  line L594 (-185.1973, 57.3557) -> (-185.507, 58.9923)
  line L595 (-185.507, 58.9923) -> (-185.8266, 62.3422)
  line L596 (-185.8266, 62.3422) -> (-185.8366, 64.0553)
  line L597 (-185.8366, 64.0553) -> (-181.8494, 64.0553)
  line L598 (-181.8494, 64.0553) -> (-181.9065, 63.3092)
  line L599 (-181.9065, 63.3092) -> (-181.9254, 62.0377)
  line L600 (-181.9254, 62.0377) -> (-181.8745, 60.6366)
  line L601 (-181.8745, 60.6366) -> (-181.7216, 58.9416)
  line L602 (-181.7216, 58.9416) -> (-181.5178, 57.3557)
  line L603 (-181.5178, 57.3557) -> (-185.1973, 57.3557)
  line L604 (-170.6235, 57) -> (-172.1256, 57.0251)
  line L605 (-172.1256, 57.0251) -> (-173.3081, 57.1)
  line L606 (-173.3081, 57.1) -> (-173.8019, 57.1662)
  line L607 (-173.8019, 57.1662) -> (-174.685, 57.3838)
  line L608 (-174.685, 57.3838) -> (-175.0739, 57.5354)
  line L609 (-175.0739, 57.5354) -> (-175.4559, 57.7333)
  line L610 (-175.4559, 57.7333) -> (-176.1391, 58.2388)
  line L611 (-176.1391, 58.2388) -> (-176.4402, 58.5461)
  line L612 (-176.4402, 58.5461) -> (-176.7207, 58.9015)
  line L613 (-176.7207, 58.9015) -> (-177.2403, 59.7903)
  line L614 (-177.2403, 59.7903) -> (-177.4788, 60.3239)
  line L615 (-177.4788, 60.3239) -> (-178.6775, 63.3161)
  line L616 (-178.6775, 63.3161) -> (-178.8991, 63.8374)
  line L617 (-178.8991, 63.8374) -> (-179.1009, 64.2831)
  line L618 (-179.1009, 64.2831) -> (-179.2896, 64.6306)
  line L619 (-179.2896, 64.6306) -> (-179.4724, 64.8502)
  line L620 (-179.4724, 64.8502) -> (-179.6672, 64.9952)
  line L621 (-179.6672, 64.9952) -> (-179.8919, 65.078)
  line L622 (-179.8919, 65.078) -> (-180.1896, 65.1169)
  line L623 (-180.1896, 65.1169) -> (-180.5951, 65.1299)
  line L624 (-180.5951, 65.1299) -> (-185.8125, 65.1299)
  line L625 (-185.8125, 65.1299) -> (-185.7005, 66.2705)
  line L626 (-185.7005, 66.2705) -> (-185.5169, 67.2393)
  line L627 (-185.5169, 67.2393) -> (-185.3919, 67.6655)
  line L628 (-185.3919, 67.6655) -> (-185.0404, 68.4267)
  line L629 (-185.0404, 68.4267) -> (-184.8138, 68.7614)
  line L630 (-184.8138, 68.7614) -> (-184.4998, 69.1088)
  line L631 (-184.4998, 69.1088) -> (-183.7139, 69.6647)
  line L632 (-183.7139, 69.6647) -> (-182.717, 70.0352)
  line L633 (-182.717, 70.0352) -> (-181.5094, 70.2203)
  line L634 (-181.5094, 70.2203) -> (-180.8267, 70.2436)
  line L635 (-180.8267, 70.2436) -> (-179.6785, 70.1924)
  line L636 (-179.6785, 70.1924) -> (-178.2489, 69.9237)
  line L637 (-178.2489, 69.9237) -> (-177.4914, 69.6166)
  line L638 (-177.4914, 69.6166) -> (-177.1712, 69.4246)
  line L639 (-177.1712, 69.4246) -> (-176.8915, 69.2178)
  line L640 (-176.8915, 69.2178) -> (-176.3802, 68.7128)
  line L641 (-176.3802, 68.7128) -> (-175.733, 67.7279)
  line L642 (-175.733, 67.7279) -> (-175.3815, 66.9197)
  line L643 (-175.3815, 66.9197) -> (-173.9752, 63.2882)
  line L644 (-173.9752, 63.2882) -> (-173.8014, 62.8697)
  line L645 (-173.8014, 62.8697) -> (-173.6398, 62.5332)
  line L646 (-173.6398, 62.5332) -> (-173.4879, 62.2824)
  line L647 (-173.4879, 62.2824) -> (-173.336, 62.1136)
  line L648 (-173.336, 62.1136) -> (-173.1552, 62.0109)
  line L649 (-173.1552, 62.0109) -> (-172.9246, 61.9579)
  line L650 (-172.9246, 61.9579) -> (-172.5861, 61.9398)
  line L651 (-172.5861, 61.9398) -> (-172.0816, 61.9339)
  line L652 (-172.0816, 61.9339) -> (-168.0426, 61.9339)
  line L653 (-168.0426, 61.9339) -> (-168.0426, 57)
  line L654 (-168.0426, 57) -> (-170.6235, 57)
  line L655 (-172.0297, 63.0085) -> (-172.0297, 70.2436)
  line L656 (-172.0297, 70.2436) -> (-168.0426, 70.2436)
  line L657 (-168.0426, 70.2436) -> (-168.0426, 63.0085)
  line L658 (-168.0426, 63.0085) -> (-172.0297, 63.0085)
  line L659 (-176.8396, 81.9568) -> (-178.6785, 81.9499)
  line L660 (-178.6785, 81.9499) -> (-179.7521, 81.929)
  line L661 (-179.7521, 81.929) -> (-180.6669, 81.852)
  line L662 (-180.6669, 81.852) -> (-181.2621, 81.7252)
  line L663 (-181.2621, 81.7252) -> (-181.4598, 81.6234)
  line L664 (-181.4598, 81.6234) -> (-181.7334, 81.3478)
  line L665 (-181.7334, 81.3478) -> (-181.8096, 81.1739)
  line L666 (-181.8096, 81.1739) -> (-181.8965, 80.6805)
  line L667 (-181.8965, 80.6805) -> (-181.9254, 79.9354)
  line L668 (-181.9254, 79.9354) -> (-181.9123, 79.5069)
  line L669 (-181.9123, 79.5069) -> (-181.8735, 78.9886)
  line L670 (-181.8735, 78.9886) -> (-185.8125, 78.9886)
  line L671 (-185.8125, 78.9886) -> (-185.8304, 79.1814)
  line L672 (-185.8304, 79.1814) -> (-185.8366, 79.4481)
  line L673 (-185.8366, 79.4481) -> (-185.8366, 79.9354)
  line L674 (-185.8366, 79.9354) -> (-185.8084, 81.2011)
  line L675 (-185.8084, 81.2011) -> (-185.5847, 83.2726)
  line L676 (-185.5847, 83.2726) -> (-185.3891, 84.0782)
  line L677 (-185.3891, 84.0782) -> (-185.1293, 84.7591)
  line L678 (-185.1293, 84.7591) -> (-184.3943, 85.832)
  line L679 (-184.3943, 85.832) -> (-183.9189, 86.2237)
  line L680 (-183.9189, 86.2237) -> (-183.4104, 86.5128)
  line L681 (-183.4104, 86.5128) -> (-182.1721, 86.9084)
  line L682 (-182.1721, 86.9084) -> (-181.4419, 87.0147)
  line L683 (-181.4419, 87.0147) -> (-179.5243, 87.1316)
  line L684 (-179.5243, 87.1316) -> (-176.8396, 87.1705)
  line L685 (-176.8396, 87.1705) -> (-174.4086, 87.1416)
  line L686 (-174.4086, 87.1416) -> (-172.6449, 87.0546)
  line L687 (-172.6449, 87.0546) -> (-171.9581, 86.9766)
  line L688 (-171.9581, 86.9766) -> (-170.7557, 86.689)
  line L689 (-170.7557, 86.689) -> (-170.24, 86.4793)
  line L690 (-170.24, 86.4793) -> (-169.737, 86.1891)
  line L691 (-169.737, 86.1891) -> (-168.926, 85.4022)
  line L692 (-168.926, 85.4022) -> (-168.6179, 84.9054)
  line L693 (-168.6179, 84.9054) -> (-168.3673, 84.3239)
  line L694 (-168.3673, 84.3239) -> (-168.0158, 82.8499)
  line L695 (-168.0158, 82.8499) -> (-167.9148, 81.9568)
  line L696 (-167.9148, 81.9568) -> (-176.8396, 81.9568)
  line L697 (-167.8389, 79.9354) -> (-167.8667, 78.6795)
  line L698 (-167.8667, 78.6795) -> (-168.0907, 76.6141)
  line L699 (-168.0907, 76.6141) -> (-168.2863, 75.8046)
  line L700 (-168.2863, 75.8046) -> (-168.5476, 75.1184)
  line L701 (-168.5476, 75.1184) -> (-169.2944, 74.0399)
  line L702 (-169.2944, 74.0399) -> (-169.7805, 73.6472)
  line L703 (-169.7805, 73.6472) -> (-170.2888, 73.358)
  line L704 (-170.2888, 73.358) -> (-171.5153, 72.9604)
  line L705 (-171.5153, 72.9604) -> (-172.2335, 72.8523)
  line L706 (-172.2335, 72.8523) -> (-174.1401, 72.7385)
  line L707 (-174.1401, 72.7385) -> (-176.8396, 72.7004)
  line L708 (-176.8396, 72.7004) -> (-179.2676, 72.7285)
  line L709 (-179.2676, 72.7285) -> (-181.0305, 72.8124)
  line L710 (-181.0305, 72.8124) -> (-181.7185, 72.8919)
  line L711 (-181.7185, 72.8919) -> (-182.921, 73.1816)
  line L712 (-182.921, 73.1816) -> (-183.4354, 73.3915)
  line L713 (-183.4354, 73.3915) -> (-183.9399, 73.6814)
  line L714 (-183.9399, 73.6814) -> (-184.7509, 74.4666)
  line L715 (-184.7509, 74.4666) -> (-185.0575, 74.9616)
  line L716 (-185.0575, 74.9616) -> (-185.3081, 75.5446)
  line L717 (-185.3081, 75.5446) -> (-185.6596, 77.0209)
  line L718 (-185.6596, 77.0209) -> (-185.7606, 77.914)
  line L719 (-185.7606, 77.914) -> (-176.8396, 77.914)
  line L720 (-176.8396, 77.914) -> (-175.0158, 77.9209)
  line L721 (-175.0158, 77.9209) -> (-173.9473, 77.9419)
  line L722 (-173.9473, 77.9419) -> (-173.0525, 78.025)
  line L723 (-173.0525, 78.025) -> (-172.4133, 78.1697)
  line L724 (-172.4133, 78.1697) -> (-172.2171, 78.2707)
  line L725 (-172.2171, 78.2707) -> (-171.9436, 78.5381)
  line L726 (-171.9436, 78.5381) -> (-171.8658, 78.7051)
  line L727 (-171.8658, 78.7051) -> (-171.7789, 79.1924)
  line L728 (-171.7789, 79.1924) -> (-171.75, 79.9354)
  line L729 (-171.75, 79.9354) -> (-171.75, 80.4468)
  line L730 (-171.75, 80.4468) -> (-171.7631, 80.6457)
  line L731 (-171.7631, 80.6457) -> (-171.8019, 80.8822)
  line L732 (-171.8019, 80.8822) -> (-167.8629, 80.8822)
  line L733 (-167.8629, 80.8822) -> (-167.845, 80.6894)
  line L734 (-167.845, 80.6894) -> (-167.8389, 80.4228)
  line L735 (-167.8389, 80.4228) -> (-167.8389, 79.9354)
  line L736 (-176.8396, 98.8318) -> (-178.6785, 98.8249)
  line L737 (-178.6785, 98.8249) -> (-179.7521, 98.804)
  line L738 (-179.7521, 98.804) -> (-180.6669, 98.727)
  line L739 (-180.6669, 98.727) -> (-181.2621, 98.6002)
  line L740 (-181.2621, 98.6002) -> (-181.4598, 98.4984)
  line L741 (-181.4598, 98.4984) -> (-181.7334, 98.2228)
  line L742 (-181.7334, 98.2228) -> (-181.8096, 98.0489)
  line L743 (-181.8096, 98.0489) -> (-181.8965, 97.5555)
  line L744 (-181.8965, 97.5555) -> (-181.9254, 96.8104)
  line L745 (-181.9254, 96.8104) -> (-181.9123, 96.3819)
  line L746 (-181.9123, 96.3819) -> (-181.8735, 95.8636)
  line L747 (-181.8735, 95.8636) -> (-185.8125, 95.8636)
  line L748 (-185.8125, 95.8636) -> (-185.8304, 96.0564)
  line L749 (-185.8304, 96.0564) -> (-185.8366, 96.3231)
  line L750 (-185.8366, 96.3231) -> (-185.8366, 96.8104)
  line L751 (-185.8366, 96.8104) -> (-185.8084, 98.0761)
  line L752 (-185.8084, 98.0761) -> (-185.5847, 100.1476)
  line L753 (-185.5847, 100.1476) -> (-185.3891, 100.9532)
  line L754 (-185.3891, 100.9532) -> (-185.1293, 101.6341)
  line L755 (-185.1293, 101.6341) -> (-184.3943, 102.707)
  line L756 (-184.3943, 102.707) -> (-183.9189, 103.0987)
  line L757 (-183.9189, 103.0987) -> (-183.4104, 103.3878)
  line L758 (-183.4104, 103.3878) -> (-182.1721, 103.7834)
  line L759 (-182.1721, 103.7834) -> (-181.4419, 103.8897)
  line L760 (-181.4419, 103.8897) -> (-179.5243, 104.0066)
  line L761 (-179.5243, 104.0066) -> (-176.8396, 104.0455)
  line L762 (-176.8396, 104.0455) -> (-174.4086, 104.0166)
  line L763 (-174.4086, 104.0166) -> (-172.6449, 103.9296)
  line L764 (-172.6449, 103.9296) -> (-171.9581, 103.8516)
  line L765 (-171.9581, 103.8516) -> (-170.7557, 103.564)
  line L766 (-170.7557, 103.564) -> (-170.24, 103.3543)
  line L767 (-170.24, 103.3543) -> (-169.737, 103.0641)
  line L768 (-169.737, 103.0641) -> (-168.926, 102.2772)
  line L769 (-168.926, 102.2772) -> (-168.6179, 101.7804)
  line L770 (-168.6179, 101.7804) -> (-168.3673, 101.1989)
  line L771 (-168.3673, 101.1989) -> (-168.0158, 99.7249)
  line L772 (-168.0158, 99.7249) -> (-167.9148, 98.8318)
  line L773 (-167.9148, 98.8318) -> (-176.8396, 98.8318)
  line L774 (-167.8389, 96.8104) -> (-167.8667, 95.5545)
  line L775 (-167.8667, 95.5545) -> (-168.0907, 93.4891)
  line L776 (-168.0907, 93.4891) -> (-168.2863, 92.6796)
  line L777 (-168.2863, 92.6796) -> (-168.5476, 91.9934)
  line L778 (-168.5476, 91.9934) -> (-169.2944, 90.9149)
  line L779 (-169.2944, 90.9149) -> (-169.7805, 90.5222)
  line L780 (-169.7805, 90.5222) -> (-170.2888, 90.233)
  line L781 (-170.2888, 90.233) -> (-171.5153, 89.8354)
  line L782 (-171.5153, 89.8354) -> (-172.2335, 89.7273)
  line L783 (-172.2335, 89.7273) -> (-174.1401, 89.6135)
  line L784 (-174.1401, 89.6135) -> (-176.8396, 89.5754)
  line L785 (-176.8396, 89.5754) -> (-179.2676, 89.6035)
  line L786 (-179.2676, 89.6035) -> (-181.0305, 89.6874)
  line L787 (-181.0305, 89.6874) -> (-181.7185, 89.7669)
  line L788 (-181.7185, 89.7669) -> (-182.921, 90.0566)
  line L789 (-182.921, 90.0566) -> (-183.4354, 90.2665)
  line L790 (-183.4354, 90.2665) -> (-183.9399, 90.5564)
  line L791 (-183.9399, 90.5564) -> (-184.7509, 91.3416)
  line L792 (-184.7509, 91.3416) -> (-185.0575, 91.8366)
  line L793 (-185.0575, 91.8366) -> (-185.3081, 92.4196)
  line L794 (-185.3081, 92.4196) -> (-185.6596, 93.8959)
  line L795 (-185.6596, 93.8959) -> (-185.7606, 94.789)
  line L796 (-185.7606, 94.789) -> (-176.8396, 94.789)
  line L797 (-176.8396, 94.789) -> (-175.0158, 94.7959)
  line L798 (-175.0158, 94.7959) -> (-173.9473, 94.8169)
  line L799 (-173.9473, 94.8169) -> (-173.0525, 94.9)
  line L800 (-173.0525, 94.9) -> (-172.4133, 95.0447)
  line L801 (-172.4133, 95.0447) -> (-172.2171, 95.1457)
  line L802 (-172.2171, 95.1457) -> (-171.9436, 95.4131)
  line L803 (-171.9436, 95.4131) -> (-171.8658, 95.5801)
  line L804 (-171.8658, 95.5801) -> (-171.7789, 96.0674)
  line L805 (-171.7789, 96.0674) -> (-171.75, 96.8104)
  line L806 (-171.75, 96.8104) -> (-171.75, 97.3218)
  line L807 (-171.75, 97.3218) -> (-171.7631, 97.5207)
  line L808 (-171.7631, 97.5207) -> (-171.8019, 97.7572)
  line L809 (-171.8019, 97.7572) -> (-167.8629, 97.7572)
  line L810 (-167.8629, 97.7572) -> (-167.845, 97.5644)
  line L811 (-167.845, 97.5644) -> (-167.8389, 97.2978)
  line L812 (-167.8389, 97.2978) -> (-167.8389, 96.8104)
  line L813 (-212.8603, 57.3557) -> (-213.17, 58.9923)
  line L814 (-213.17, 58.9923) -> (-213.4896, 62.3422)
  line L815 (-213.4896, 62.3422) -> (-213.4995, 64.0553)
  line L816 (-213.4995, 64.0553) -> (-209.5124, 64.0553)
  line L817 (-209.5124, 64.0553) -> (-209.5694, 63.3092)
  line L818 (-209.5694, 63.3092) -> (-209.5884, 62.0377)
  line L819 (-209.5884, 62.0377) -> (-209.5375, 60.6366)
  line L820 (-209.5375, 60.6366) -> (-209.3846, 58.9416)
  line L821 (-209.3846, 58.9416) -> (-209.1808, 57.3557)
  line L822 (-209.1808, 57.3557) -> (-212.8603, 57.3557)
  line L823 (-198.2865, 57) -> (-199.7886, 57.0251)
  line L824 (-199.7886, 57.0251) -> (-200.9711, 57.1)
  line L825 (-200.9711, 57.1) -> (-201.4648, 57.1662)
  line L826 (-201.4648, 57.1662) -> (-202.348, 57.3838)
  line L827 (-202.348, 57.3838) -> (-202.7369, 57.5354)
  line L828 (-202.7369, 57.5354) -> (-203.1188, 57.7333)
  line L829 (-203.1188, 57.7333) -> (-203.802, 58.2388)
  line L830 (-203.802, 58.2388) -> (-204.1032, 58.5461)
  line L831 (-204.1032, 58.5461) -> (-204.3837, 58.9015)
  line L832 (-204.3837, 58.9015) -> (-204.9032, 59.7903)
  line L833 (-204.9032, 59.7903) -> (-205.1418, 60.3239)
  line L834 (-205.1418, 60.3239) -> (-206.3404, 63.3161)
  line L835 (-206.3404, 63.3161) -> (-206.5621, 63.8374)
  line L836 (-206.5621, 63.8374) -> (-206.7638, 64.2831)
  line L837 (-206.7638, 64.2831) -> (-206.9525, 64.6306)
  line L838 (-206.9525, 64.6306) -> (-207.1353, 64.8502)
  line L839 (-207.1353, 64.8502) -> (-207.3302, 64.9952)
  line L840 (-207.3302, 64.9952) -> (-207.5549, 65.078)
  line L841 (-207.5549, 65.078) -> (-207.8525, 65.1169)
  line L842 (-207.8525, 65.1169) -> (-208.258, 65.1299)
  line L843 (-208.258, 65.1299) -> (-213.4755, 65.1299)
  line L844 (-213.4755, 65.1299) -> (-213.3635, 66.2705)
  line L845 (-213.3635, 66.2705) -> (-213.1799, 67.2393)
  line L846 (-213.1799, 67.2393) -> (-213.0549, 67.6655)
  line L847 (-213.0549, 67.6655) -> (-212.7033, 68.4267)
  line L848 (-212.7033, 68.4267) -> (-212.4768, 68.7614)
  line L849 (-212.4768, 68.7614) -> (-212.1628, 69.1088)
  line L850 (-212.1628, 69.1088) -> (-211.3769, 69.6647)
  line L851 (-211.3769, 69.6647) -> (-210.38, 70.0352)
  line L852 (-210.38, 70.0352) -> (-209.1724, 70.2203)
  line L853 (-209.1724, 70.2203) -> (-208.4897, 70.2436)
  line L854 (-208.4897, 70.2436) -> (-207.3414, 70.1924)
  line L855 (-207.3414, 70.1924) -> (-205.9119, 69.9237)
  line L856 (-205.9119, 69.9237) -> (-205.1543, 69.6166)
  line L857 (-205.1543, 69.6166) -> (-204.8342, 69.4246)
  line L858 (-204.8342, 69.4246) -> (-204.5545, 69.2178)
  line L859 (-204.5545, 69.2178) -> (-204.0431, 68.7128)
  line L860 (-204.0431, 68.7128) -> (-203.396, 67.7279)
  line L861 (-203.396, 67.7279) -> (-203.0444, 66.9197)
  line L862 (-203.0444, 66.9197) -> (-201.6382, 63.2882)
  line L863 (-201.6382, 63.2882) -> (-201.4643, 62.8697)
  line L864 (-201.4643, 62.8697) -> (-201.3027, 62.5332)
  line L865 (-201.3027, 62.5332) -> (-201.1509, 62.2824)
  line L866 (-201.1509, 62.2824) -> (-200.999, 62.1136)
  line L867 (-200.999, 62.1136) -> (-200.8182, 62.0109)
  line L868 (-200.8182, 62.0109) -> (-200.5876, 61.9579)
  line L869 (-200.5876, 61.9579) -> (-200.2491, 61.9398)
  line L870 (-200.2491, 61.9398) -> (-199.7446, 61.9339)
  line L871 (-199.7446, 61.9339) -> (-195.7056, 61.9339)
  line L872 (-195.7056, 61.9339) -> (-195.7056, 57)
  line L873 (-195.7056, 57) -> (-198.2865, 57)
  line L874 (-199.6927, 63.0085) -> (-199.6927, 70.2436)
  line L875 (-199.6927, 70.2436) -> (-195.7056, 70.2436)
  line L876 (-195.7056, 70.2436) -> (-195.7056, 63.0085)